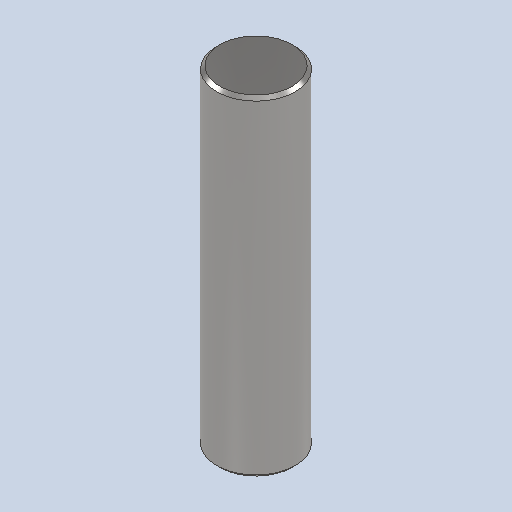
# Autodesk Inventor part: Bolzen
Saved by Autodesk Inventor 2027.1 (Build 311270010, 270A)
## iProperties
Created: 2026-07-29
Part Number: Bolzen
Material: Stahl, Legierung
Document SubType Name: Modeling
Designer: moest
Density: 7.73 g/cm^3
Appearance: Halbpoliert
Author: moest
Autodesk Inventor part; units mm, degrees
ref_plane "YZ Plane" through (0, 0, 0) normal (1, 0, 0) x (0, 1, 0)
ref_plane "XZ Plane" through (0, 0, 0) normal (0, 1, 0) x (-1, 0, 0)
ref_plane "XY Plane" through (0, 0, 0) normal (0, 0, 1) x (1, 0, 0)
sketch "Skizze1" plane through (0, 0, 0) normal (0, 0, 1) x (1, 0, 0)
  circle A0 centre (0, 0) radius 12.5
  dimension "d0" = 25
  constraints: 1 centre point, 1 coincident
  measures "d0" diameter of A0
extrude "Extrusion1" add sketch "Skizze1" along normal blind 105
chamfer "Fasen1" distance 1 angle 45 2 edges at (-12.5, 0, 105) (-12.5, 0, 0)
